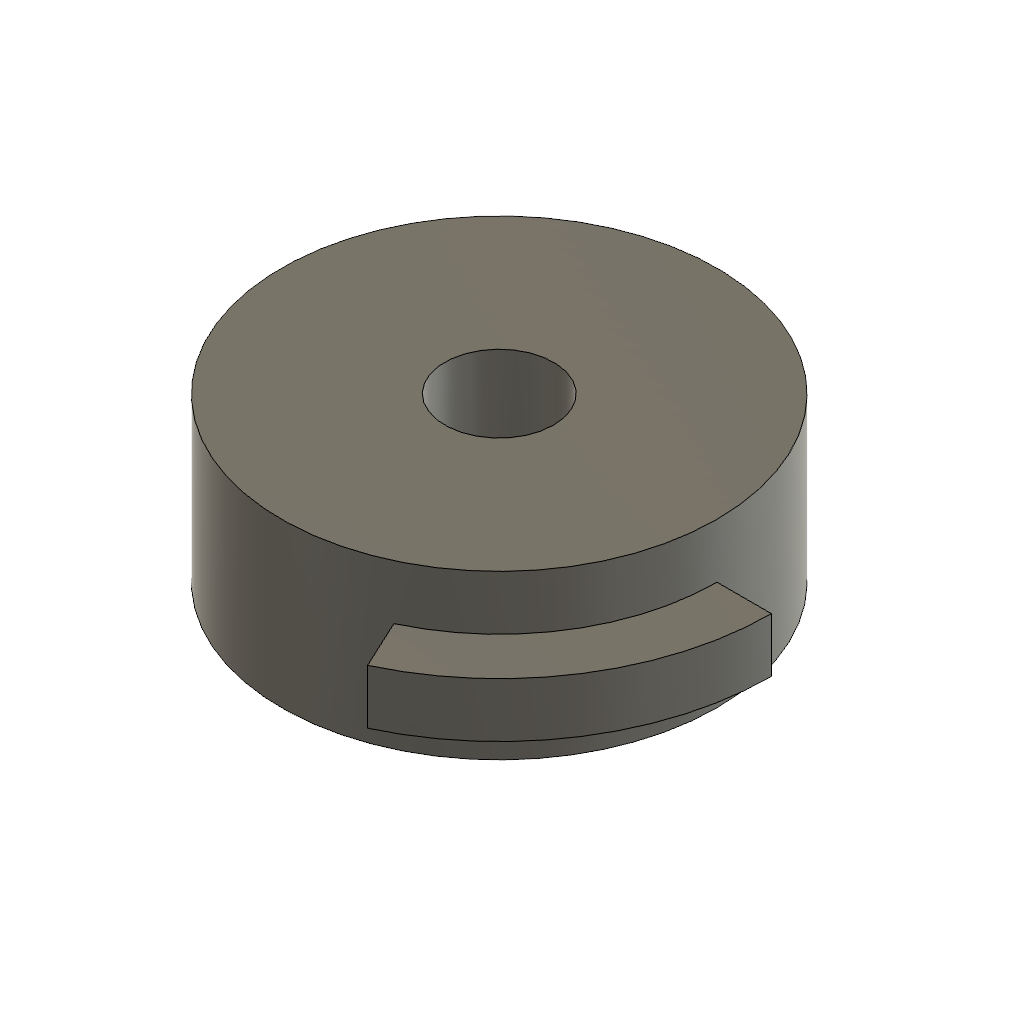
join (Autodesk Fusion 360 design; units mm, degrees)
part number: 2026-10-20-19-34-06-684
Autodesk Fusion 360 part; units mm, degrees
sketch "Sketch1" plane through (0, 0, 0) normal (0, 0, 1) x (1, 0, 0)
  line L0 (10, 0) -> (40, 0)
  line L1 (40, 0) -> (40, 30)
  line L2 (40, 30) -> (10, 30)
  line L3 (10, 30) -> (10, 0)
revolve "Revolve1" add sketch "Sketch1" angle 360 about axis through (0, 1.75, 0) along (0, 1, 0)
sketch "ProbeRevolveProfile" plane through (0, 0, 0) normal (0, 0, 1) x (1, 0, 0)
  line L0 (20, 10) -> (50, 10)
  line L1 (50, 10) -> (50, 20)
  line L2 (50, 20) -> (20, 20)
  line L3 (20, 20) -> (20, 10)
revolve "ProbeRevolve" add sketch "ProbeRevolveProfile" angle 65 about axis through (0, 1.75, 0) along (0, -1, 0)
